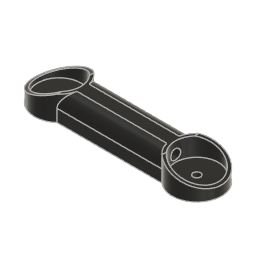
Elbow (Autodesk Fusion 360 design; units mm, degrees)
Autodesk Fusion 360 part; units mm, degrees
sketch "Sketch1" plane through (0, 0, 0) normal (0, 0, 1) x (1, 0, 0)
  circle A0 centre (0, 0) radius 20
  circle A1 centre (0, 0) radius 17.5
  line L0 (13.2288, 15) -> (55.7288, 15)
  line L1 (55.7288, 15) -> (55.7288, -15)
  line L2 (55.7288, -15) -> (13.2288, -15)
  circle A2 centre (0, 0) radius 3
  line L3 (13.2288, -15) -> (13.2288, 15)
  dimension "d97" = 40
  dimension "d99" = 15
  dimension "d100" = 42.5
  dimension "d101" = 30
  dimension "d102" = 42.5
  dimension "d103" = 6
  dimension "d104" = 35
  constraint coincident A0.centre A1.centre
  constraint coincident A0 L0.start
  constraint horizontal L0
  constraint perpendicular L0 L1
  constraint horizontal L2
  measures "d97" diameter of A0
  measures "d99" distance of A0.centre L0
  measures "d100" distance of L0.start L0.end
  measures "d101" distance of L0.end L1.end
  measures "d102" distance of L1.end L2.end
  measures "d103" diameter of A2
  measures "d104" diameter of A1
extrude "Extrude1" add sketch "Sketch1" along normal blind 20 contours A0 A1 L3 | A0 L0 L1 L2 | A0 A1 L3
extrude "Extrude2" add sketch "Sketch1" along normal blind 5 contours A1 L3 | A1 L3
sketch "Sketch2" plane through (0, 0, 20) normal (0, 0, 1) x (-1, 0, 0)
  circle A0 centre (0, 0) radius 17.5
  arc A1 (-13.2288, -15) -> (-13.2288, 15) centre (0, 0) ccw
  line L0 (-13.2288, 15) -> (-55.7288, 15)
  line L1 (-55.7288, 15) -> (-55.7288, -15)
  line L2 (-55.7288, -15) -> (-13.2288, -15)
  line L3 (-55.7288, 15) -> (-13.2288, 15)
  line L4 (-13.2288, 15) -> (-13.2288, -15)
  line L5 (-55.7288, -15) -> (-55.7288, 15)
  line L6 (-13.2288, -15) -> (-55.7288, -15)
ref_plane "WorkPlane1" through (13.2288, 0, 20) normal (-0.34202, 0, 0.939693) x (0, 1, 0)
sketch "Sketch3" plane through (-4.8804, 0, 13.4088) normal (-0.34202, 0, 0.939693) x (0, 1, 0)
  line L0 (25, 25) -> (-25, 25)
  line L1 (-25, 25) -> (-25, -25)
  line L2 (-25, -25) -> (25, -25)
  line L3 (25, -25) -> (25, 25)
  line L4 (25, 25) -> (-25, -25) construction
  line L5 (-25, 25) -> (25, -25) construction
  dimension "d111" = 50
  dimension "d115" = 50
  constraint horizontal L0
  constraint perpendicular L0 L1
  constraint parallel L0 L2
  constraint parallel L1 L3
  constraint coincident L4 origin
  constraint coincident L5 origin
  measures "d111" distance of L1.end L2.end
  measures "d115" distance of L0.end L1.end
extrude "Extrude3" cut sketch "Sketch3" along normal blind 15
fillet "Fillet1" radius 10 2 edges at (34.4788, 15, 20) (34.4788, -15, 20)
sketch "Sketch4" plane through (55.7288, 0, 0) normal (1, 0, 0) x (0, 1, 0)
  arc A0 (-5, 20) -> (-15, 10) centre (-5, 10) ccw
  line L0 (-15, 10) -> (-15, 0)
  line L1 (-15, 0) -> (15, 0)
  line L2 (15, 0) -> (15, 10)
  arc A1 (15, 10) -> (5, 20) centre (5, 10) ccw
  line L3 (5, 20) -> (-5, 20)
  circle A2 centre (0, 10.5984) radius 4
  dimension "d119" = 15
  dimension "d122" = 8
  measures "d119" distance of L0 A2.centre
  measures "d122" diameter of A2
extrude "Extrude4" cut sketch "Sketch4" against normal blind 53 contours A2
ref_plane "WorkPlane2" through (55.7288, 0, 10) normal (1, 0, 0) x (0, 1, 0)
mirror "Mirror1" about plane through (55.7288, 0, 10) normal (1, 0, 0) of bodies 1 merged
